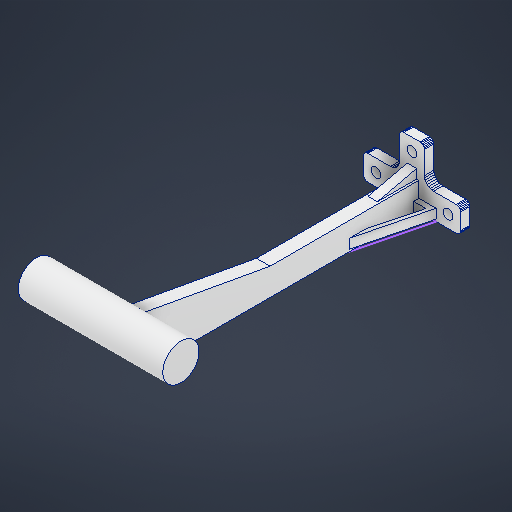
# Autodesk Inventor part: clean_handle_test
Saved by Autodesk Inventor 2026.4 (Build 304435000, 435)
## iProperties
Created: 2026-11-07
Part Number: clean_handle_test
Material: Alumínio 6061
Document SubType Name: Modeling
Designer: User
Density: 2.7 g/cm^3
Appearance: Alumínio - Plano
Author: User
Autodesk Inventor part; units mm, degrees
ref_plane "YZ Plane" through (0, 0, 0) normal (1, 0, 0) x (0, 1, 0)
ref_plane "XY Plane" through (0, 0, 0) normal (0, 0, 1) x (1, 0, 0)
sketch "Esboço1" plane through (0, 0, 0) normal (0, 0, 1) x (1, 0, 0)
  line L0 (-33.7546, 1.524) -> (-34.0591, 2.2591)
  line L1 (-34.0591, 2.2591) -> (-34.163, 3.048)
  line L2 (-34.163, 3.048) -> (-34.163, 14.478)
  line L3 (-34.163, 14.478) -> (-34.0591, 15.2669)
  line L4 (-34.0591, 15.2669) -> (-33.7546, 16.002)
  line L5 (-33.7546, 16.002) -> (-33.2703, 16.6333)
  line L6 (-33.2703, 16.6333) -> (-32.639, 17.1176)
  line L7 (-32.639, 17.1176) -> (-31.9039, 17.4221)
  line L8 (-31.9039, 17.4221) -> (-31.115, 17.526)
  line L9 (-31.115, 17.526) -> (-15.113, 17.526)
  line L10 (-15.113, 17.526) -> (-13.8742, 17.648)
  line L11 (-13.8742, 17.648) -> (-12.683, 18.0094)
  line L12 (-12.683, 18.0094) -> (-11.5851, 18.5962)
  line L13 (-11.5851, 18.5962) -> (-10.6229, 19.3859)
  line L14 (-10.6229, 19.3859) -> (-9.8332, 20.3481)
  line L15 (-9.8332, 20.3481) -> (-9.2464, 21.446)
  line L16 (-9.2464, 21.446) -> (-8.885, 22.6372)
  line L17 (-8.885, 22.6372) -> (-8.763, 23.876)
  line L18 (-8.763, 23.876) -> (-8.763, 39.878)
  line L19 (-8.763, 39.878) -> (-8.6591, 40.6669)
  line L20 (-8.6591, 40.6669) -> (-8.3546, 41.402)
  line L21 (-8.3546, 41.402) -> (-7.8703, 42.0333)
  line L22 (-7.8703, 42.0333) -> (-7.239, 42.5176)
  line L23 (-7.239, 42.5176) -> (-6.5039, 42.8221)
  line L24 (-6.5039, 42.8221) -> (-5.715, 42.926)
  line L25 (-5.715, 42.926) -> (5.715, 42.926)
  line L26 (5.715, 42.926) -> (6.5039, 42.8221)
  line L27 (6.5039, 42.8221) -> (7.239, 42.5176)
  line L28 (7.239, 42.5176) -> (7.8703, 42.0333)
  line L29 (7.8703, 42.0333) -> (8.3546, 41.402)
  line L30 (8.3546, 41.402) -> (8.6591, 40.6669)
  line L31 (8.6591, 40.6669) -> (8.763, 39.878)
  line L32 (8.763, 39.878) -> (8.763, 23.876)
  line L33 (8.763, 23.876) -> (8.885, 22.6372)
  line L34 (8.885, 22.6372) -> (9.2464, 21.446)
  line L35 (9.2464, 21.446) -> (9.8332, 20.3481)
  line L36 (9.8332, 20.3481) -> (10.6229, 19.3859)
  line L37 (10.6229, 19.3859) -> (11.5851, 18.5962)
  line L38 (11.5851, 18.5962) -> (12.683, 18.0094)
  line L39 (12.683, 18.0094) -> (13.8742, 17.648)
  line L40 (13.8742, 17.648) -> (15.113, 17.526)
  line L41 (15.113, 17.526) -> (31.115, 17.526)
  line L42 (31.115, 17.526) -> (31.9039, 17.4221)
  line L43 (31.9039, 17.4221) -> (32.639, 17.1176)
  line L44 (32.639, 17.1176) -> (33.2703, 16.6333)
  line L45 (33.2703, 16.6333) -> (33.7546, 16.002)
  line L46 (33.7546, 16.002) -> (34.0591, 15.2669)
  line L47 (34.0591, 15.2669) -> (34.163, 14.478)
  line L48 (34.163, 14.478) -> (34.163, 3.048)
  line L49 (34.163, 3.048) -> (34.0591, 2.2591)
  line L50 (34.0591, 2.2591) -> (33.7546, 1.524)
  line L51 (33.7546, 1.524) -> (33.2703, 0.8927)
  line L52 (33.2703, 0.8927) -> (32.639, 0.4084)
  line L53 (32.639, 0.4084) -> (31.9039, 0.1039)
  line L54 (31.9039, 0.1039) -> (31.115, 0)
  line L55 (31.115, 0) -> (-31.115, 0)
  line L56 (-31.115, 0) -> (-31.9039, 0.1039)
  line L57 (-31.9039, 0.1039) -> (-32.639, 0.4084)
  line L58 (-32.639, 0.4084) -> (-33.2703, 0.8927)
  line L59 (-33.2703, 0.8927) -> (-33.7546, 1.524)
  circle A0 centre (-25.4, 8.763) radius 3.3655
  circle A1 centre (25.4, 8.763) radius 3.3655
  circle A2 centre (0, 34.163) radius 3.3655
  constraints: 120 end point, 3 centre point
extrude "Base_Plate" add sketch "Esboço1" along normal blind 6.604
sketch "Esboço2" plane through (0, 0, 0) normal (1, 0, 0) x (0, 1, 0)
  line L0 (19.05, 6.604) -> (0, 6.604)
  line L1 (0, 6.604) -> (0, 168.0718)
  line L2 (0, 168.0718) -> (0.0829, 170.7854)
  line L3 (0.0829, 170.7854) -> (0.3313, 173.4889)
  line L4 (0.3313, 173.4889) -> (0.7443, 176.1722)
  line L5 (0.7443, 176.1722) -> (1.3204, 178.8252)
  line L6 (1.3204, 178.8252) -> (2.0573, 181.4382)
  line L7 (2.0573, 181.4382) -> (2.9524, 184.0013)
  line L8 (2.9524, 184.0013) -> (4.0022, 186.5049)
  line L9 (4.0022, 186.5049) -> (5.203, 188.9398)
  line L10 (5.203, 188.9398) -> (6.5501, 191.2969)
  line L11 (6.5501, 191.2969) -> (8.0387, 193.5673)
  line L12 (8.0387, 193.5673) -> (25.1587, 218.0234)
  line L13 (25.1587, 218.0234) -> (35.085, 199.2097)
  line L14 (35.085, 199.2097) -> (19.05, 111.1826)
  line L15 (19.05, 111.1826) -> (19.05, 6.604)
  constraints: 32 end point
extrude "Central_Stem" add sketch "Esboço2" along normal mid plane 9.652
sketch "Esboço3" plane through (0, 0, 0) normal (1, 0, 0) x (0, 1, 0)
  circle A0 centre (38.1, 219.888) radius 12.7
  constraints: 1 centre point
extrude "Handle_Bar" add sketch "Esboço3" along normal mid plane 101.6
sketch "Esboço4" plane through (0, 0, 0) normal (0, 1, 0) x (-1, 0, 0)
  line L0 (-16.9799, 6.604) -> (-4.826, 6.604)
  line L1 (-4.826, 6.604) -> (-4.826, 55.4431)
  line L2 (-4.826, 55.4431) -> (-16.9799, 6.604)
  line L3 (16.9799, 6.604) -> (4.826, 6.604)
  line L4 (4.826, 6.604) -> (4.826, 55.4431)
  line L5 (4.826, 55.4431) -> (16.9799, 6.604)
  constraints: 12 end point
ref_plane "Plano de trabalho1" through (0, 1.524, 0) normal (0, 1, 0) x (-1, 0, 0)
sketch "Esboço5" plane through (0, 1.524, 0) normal (0, 1, 0) x (-1, 0, 0)
  line L0 (-16.9799, 6.604) -> (-4.826, 6.604)
  line L1 (-4.826, 6.604) -> (-4.826, 55.4431)
  line L2 (-4.826, 55.4431) -> (-16.9799, 6.604)
  line L3 (16.9799, 6.604) -> (4.826, 6.604)
  line L4 (4.826, 6.604) -> (4.826, 55.4431)
  line L5 (4.826, 55.4431) -> (16.9799, 6.604)
  constraints: 12 end point
extrude "Side_Gussets" add sketch "Esboço5" along normal blind 6.604
sketch "Esboço6" plane through (0, 1.524, 0) normal (0, 1, 0) x (-1, 0, 0)
  line L0 (-13.5636, 10.3124) -> (-4.826, 10.3124)
  line L1 (-4.826, 10.3124) -> (-4.826, 43.688)
  line L2 (-4.826, 43.688) -> (-13.5636, 10.3124)
  line L3 (13.5636, 10.3124) -> (4.826, 10.3124)
  line L4 (4.826, 10.3124) -> (4.826, 43.688)
  line L5 (4.826, 43.688) -> (13.5636, 10.3124)
  constraints: 12 end point
extrude "Gusset_Lightening_Pockets" cut sketch "Esboço6" along normal blind 6.604
sketch "Esboço7" plane through (0, 0, 0) normal (1, 0, 0) x (0, 1, 0)
  line L0 (19.05, 6.604) -> (25.5194, 6.604)
  line L1 (25.5194, 6.604) -> (19.05, 34.2392)
  line L2 (19.05, 34.2392) -> (19.05, 6.604)
  constraints: 6 end point
extrude "Rear_Support_Rib" add sketch "Esboço7" along normal mid plane 6.604
